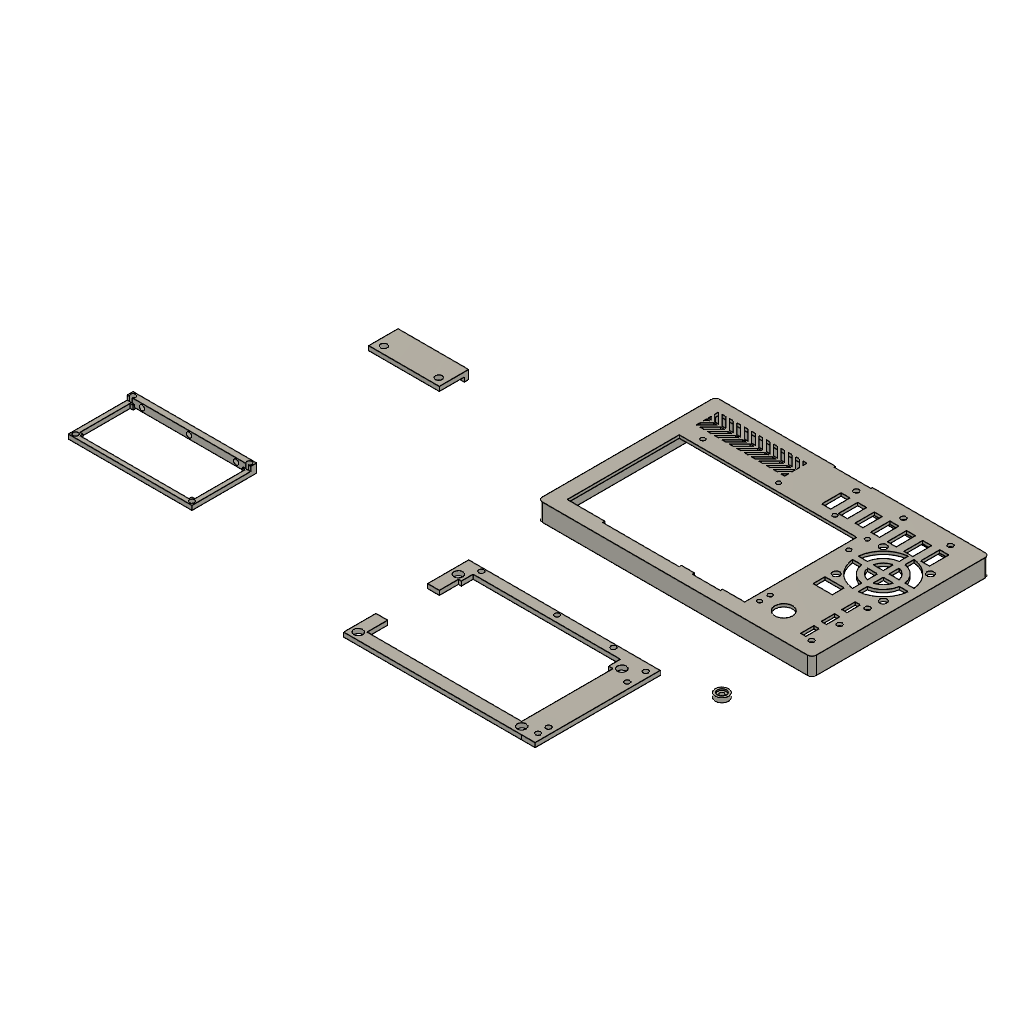
Cyberdeck V1.0 (Autodesk Fusion 360 design; units mm, degrees)
part number: 2026-10-02-13-29-24-381
part number: 2026-10-02-20-17-14-909
part number: 2026-10-03-23-10-58-900
part number: 2026-10-04-18-41-37-059
part number: 2026-10-05-15-20-19-140
part number: 2026-10-05-15-29-06-414
Autodesk Fusion 360 part; units mm, degrees
(part 1 of 2)
sketch "Sketch1" plane through (0, 0, 0) normal (0, 1, 0) x (1, 0, 0)
  line L0 (3, 0) -> (183.15, 0)
  line L1 (186.15, 3) -> (186.15, 117.65)
  line L2 (183.15, 120.65) -> (3, 120.65)
  line L3 (0, 117.65) -> (0, 3)
  arc A0 (3, 120.65) -> (0, 117.65) centre (3, 117.65) ccw
  arc A1 (0, 3) -> (3, 0) centre (3, 3) ccw
  arc A2 (186.15, 117.65) -> (183.15, 120.65) centre (183.15, 117.65) ccw
  arc A3 (183.15, 0) -> (186.15, 3) centre (183.15, 3) ccw
  line L4 (93.075, 120.65) -> (93.075, 0) construction
  line L5 (0, 60.325) -> (186.15, 60.325) construction
  line L6 (0, 80) -> (10, 80) construction
  line L7 (10, 80) -> (10, 60.325) construction
  line L8 (131.5, 0) -> (131.5, 10) construction
  line L9 (131.5, 10) -> (11, 10)
  line L10 (11, 10) -> (11, 86) construction
  line L11 (11, 86) -> (131.5, 86)
  line L12 (131.5, 86) -> (131.5, 10)
  line L13 (93.075, 114.9634) -> (105.575, 114.9634) construction
  line L14 (106.575, 120.65) -> (106.575, 123.65) construction
  line L15 (106.575, 120.65) -> (81.575, 120.65)
  line L16 (81.575, 120.65) -> (81.575, 119.65)
  line L17 (81.575, 119.65) -> (106.575, 119.65)
  line L18 (106.575, 119.65) -> (106.575, 120.65)
  line L19 (131.5, 15.7843) -> (116.5, 15.7843) construction
  line L20 (115.5, 10) -> (115.5, 8.5) construction
  line L21 (115.5, 8.5) -> (96.5, 8.5)
  line L22 (96.5, 8.5) -> (96.5, 10)
  line L23 (96.5, 10) -> (115.5, 10)
  line L24 (115.5, 10) -> (115.5, 8.5)
  line L25 (96.5, 8.5) -> (85.5, 8.5) construction
  line L26 (87.5, 10) -> (35.5, 10)
  line L27 (35.5, 10) -> (35.5, 8.5)
  line L28 (35.5, 8.5) -> (87.5, 8.5)
  line L29 (87.5, 8.5) -> (87.5, 10)
  line L30 (182.15, 116.65) -> (4, 116.65)
  line L31 (4, 116.65) -> (4, 4)
  line L32 (4, 4) -> (182.15, 4)
  line L33 (182.15, 4) -> (182.15, 116.65)
  line L34 (181.1, 53.5082) -> (141.1, 53.5082) construction
  line L35 (141.1, 53.5082) -> (141.1, 93.5082) construction
  line L36 (141.1, 93.5082) -> (181.1, 93.5082) construction
  line L37 (181.1, 93.5082) -> (181.1, 53.5082) construction
  line L38 (181.1, 73.5082) -> (141.1, 73.5082) construction
  line L39 (161.1, 93.5082) -> (161.1, 53.5082) construction
  line L40 (177.1, 53.5082) -> (177.1, 57.5082) construction
  circle A4 centre (177.1, 57.5082) radius 2.4
  line L41 (141.1, 57.4958) -> (145.1, 57.4958) construction
  line L42 (145.1, 53.5082) -> (145.1, 57.5082) construction
  circle A5 centre (145.1, 57.5082) radius 2.4
  circle A6 centre (145.1, 89.5082) radius 2.4
  circle A7 centre (177.1, 89.5082) radius 2.4
  line L43 (159.1, 92.4026) -> (159.1, 86.3534)
  line L44 (159.1, 82.2831) -> (159.1, 75.5082)
  line L45 (163.1, 92.4026) -> (163.1, 86.3534)
  line L46 (163.1, 82.2831) -> (163.1, 75.5082)
  line L47 (163.1, 71.5082) -> (163.1, 64.7332)
  line L48 (163.1, 60.6629) -> (163.1, 54.6137)
  line L49 (159.1, 71.5082) -> (159.1, 64.7332)
  line L50 (159.1, 60.6629) -> (159.1, 54.6137)
  line L51 (179.9944, 71.5082) -> (173.9452, 71.5082)
  arc A8 (163.1, 64.7332) -> (169.875, 71.5082) centre (161.1, 73.5082) ccw
  arc A9 (169.875, 75.5082) -> (163.1, 82.2831) centre (161.1, 73.5082) ccw
  arc A10 (163.1, 60.6629) -> (173.9452, 71.5082) centre (161.1, 73.5082) ccw
  arc A11 (173.9452, 75.5082) -> (163.1, 86.3534) centre (161.1, 73.5082) ccw
  line L52 (179.9944, 75.5082) -> (173.9452, 75.5082)
  line L53 (169.875, 75.5082) -> (163.1, 75.5082)
  line L54 (148.2548, 71.5082) -> (142.2056, 71.5082)
  arc A12 (159.1, 86.3534) -> (148.2548, 75.5082) centre (161.1, 73.5082) ccw
  arc A13 (148.2548, 71.5082) -> (159.1, 60.6629) centre (161.1, 73.5082) ccw
  arc A14 (159.1, 82.2831) -> (152.325, 75.5082) centre (161.1, 73.5082) ccw
  arc A15 (152.325, 71.5082) -> (159.1, 64.7332) centre (161.1, 73.5082) ccw
  line L55 (159.1, 75.5082) -> (152.325, 75.5082)
  line L56 (148.2548, 75.5082) -> (142.2056, 75.5082)
  arc A16 (163.1, 54.6137) -> (179.9944, 71.5082) centre (161.1, 73.5082) ccw
  arc A17 (142.2056, 71.5082) -> (159.1, 54.6137) centre (161.1, 73.5082) ccw
  arc A18 (179.9944, 75.5082) -> (163.1, 92.4026) centre (161.1, 73.5082) ccw
  arc A19 (159.1, 92.4026) -> (142.2056, 75.5082) centre (161.1, 73.5082) ccw
  line L57 (169.875, 71.5082) -> (163.1, 71.5082)
  line L58 (159.1, 71.5082) -> (152.325, 71.5082)
  line L59 (9.9994, 116.65) -> (9.9994, 112.65) construction
  line L60 (9.9994, 112.65) -> (5.9994, 112.65) construction
  line L61 (9.9994, 112.65) -> (69.9994, 112.65)
  line L62 (69.9994, 112.65) -> (69.9994, 97.65)
  line L63 (69.9994, 97.65) -> (9.9994, 97.65)
  line L64 (9.9994, 97.65) -> (9.9994, 112.65)
  line L65 (9.9994, 105.15) -> (69.9994, 105.15) construction
  line L66 (39.9994, 112.65) -> (39.9994, 97.65) construction
  line L67 (9.9994, 112.65) -> (17.4994, 105.15)
  line L68 (9.9994, 112.65) -> (20.6066, 112.65) construction
  line L69 (19.9994, 105.1486) -> (12.498, 112.65)
  line L70 (19.9994, 105.1486) -> (9.3934, 105.1486) construction
  line L71 (14.9994, 105.1486) -> (9.9994, 110.1486)
  line L72 (14.9994, 105.1486) -> (7.9289, 105.1486) construction
  line L73 (12.4994, 105.1486) -> (9.9994, 107.6486)
  line L74 (12.4994, 105.1486) -> (8.9645, 105.1486) construction
  line L75 (22.4994, 105.149) -> (14.9984, 112.65)
  line L76 (22.4994, 105.149) -> (11.8934, 105.149) construction
  line L77 (24.9994, 105.1493) -> (17.4987, 112.65)
  line L78 (24.9994, 105.1493) -> (14.3934, 105.1493) construction
  line L79 (27.4994, 105.1496) -> (19.9991, 112.65)
  line L80 (27.4994, 105.1496) -> (16.8934, 105.1496) construction
  line L81 (29.9994, 105.15) -> (22.4994, 112.65)
  line L82 (29.9994, 105.15) -> (19.3934, 105.15) construction
  line L83 (32.4994, 105.15) -> (24.9994, 112.65)
  line L84 (32.4994, 105.15) -> (21.8934, 105.15) construction
  line L85 (34.9994, 105.15) -> (27.4994, 112.65)
  line L86 (34.9994, 105.15) -> (24.3934, 105.15) construction
  line L87 (37.4994, 105.15) -> (29.9994, 112.65)
  line L88 (37.4994, 105.15) -> (26.8934, 105.15) construction
  line L89 (39.9994, 105.15) -> (32.5001, 112.65)
  line L90 (12.4994, 105.1514) -> (9.9994, 102.6514)
  line L91 (14.9994, 105.1514) -> (9.9994, 100.1514)
  line L92 (9.9994, 97.65) -> (17.4994, 105.15)
  line L93 (19.9994, 105.1514) -> (12.498, 97.65)
  line L94 (22.4994, 105.151) -> (14.9984, 97.65)
  line L95 (24.9994, 105.1507) -> (17.4987, 97.65)
  line L96 (27.4994, 105.1504) -> (19.9991, 97.65)
  line L97 (29.9994, 105.15) -> (22.4994, 97.65)
  line L98 (32.4994, 105.15) -> (24.9994, 97.65)
  line L99 (34.9994, 105.15) -> (27.4994, 97.65)
  line L100 (37.4994, 105.15) -> (29.9994, 97.65)
  line L101 (39.9994, 105.15) -> (32.5001, 97.65)
  line L102 (44.9994, 105.15) -> (37.5001, 112.65)
  line L103 (44.9994, 105.15) -> (37.5001, 97.65)
  line L104 (42.4994, 105.15) -> (34.9994, 97.65)
  line L105 (42.4994, 105.15) -> (34.9994, 112.65)
  line L106 (49.9994, 105.15) -> (42.5001, 112.65)
  line L107 (49.9994, 105.15) -> (42.5001, 97.65)
  line L108 (47.4994, 105.15) -> (39.9994, 97.65)
  line L109 (47.4994, 105.15) -> (39.9994, 112.65)
  line L110 (54.9994, 105.15) -> (47.5001, 112.65)
  line L111 (54.9994, 105.15) -> (47.5001, 97.65)
  line L112 (52.4994, 105.15) -> (44.9994, 97.65)
  line L113 (52.4994, 105.15) -> (44.9994, 112.65)
  line L114 (59.9994, 105.15) -> (52.5001, 112.65)
  line L115 (59.9994, 105.15) -> (52.5001, 97.65)
  line L116 (57.4994, 105.15) -> (49.9994, 97.65)
  line L117 (57.4994, 105.15) -> (49.9994, 112.65)
  line L118 (64.9994, 105.15) -> (57.5001, 112.65)
  line L119 (64.9994, 105.15) -> (57.5001, 97.65)
  line L120 (62.4994, 105.15) -> (54.9994, 97.65)
  line L121 (62.4994, 105.15) -> (54.9994, 112.65)
  line L122 (69.9994, 105.15) -> (62.5001, 112.65)
  line L123 (69.9994, 105.15) -> (62.5001, 97.65)
  line L124 (67.4994, 105.15) -> (59.9994, 97.65)
  line L125 (67.4994, 105.15) -> (59.9994, 112.65)
  line L126 (64.9998, 112.65) -> (69.9994, 107.6504)
  line L127 (64.9998, 112.65) -> (72.0711, 112.65) construction
  line L128 (67.5003, 112.65) -> (69.9994, 110.1508)
  line L129 (67.5003, 112.65) -> (71.0353, 112.65) construction
  line L130 (67.5003, 97.65) -> (69.9994, 100.1492)
  line L131 (64.9998, 97.65) -> (69.9994, 102.6496)
  line L132 (9.849, 105.1486) -> (9.849, 105.6486) construction
  line L133 (9.9994, 105.65) -> (69.9994, 105.65)
  line L134 (69.9994, 105.65) -> (69.9994, 104.65)
  line L135 (69.9994, 104.65) -> (9.9994, 104.65)
  line L136 (9.9994, 104.65) -> (9.9994, 105.65)
  circle A20 centre (149, 18) radius 6
  line L137 (149, 18) -> (149, 39) construction
  line L138 (149, 39) -> (149, -1.5) construction
  line L139 (149, 39) -> (157.5, 39) construction
  line L140 (157.5, 39) -> (140.5, 39) construction
  line L141 (140.5, 39) -> (140.5, -2) construction
  line L142 (140.5, -2) -> (157.5, -2) construction
  line L143 (157.5, -2) -> (157.5, 39) construction
  line L144 (10, 86) -> (130.5, 86)
  line L145 (130.5, 45.25) -> (130.5, 69.25)
  line L146 (135.5, 16) -> (130.5, 16) construction
  line L147 (130.5, 86) -> (130.5, 10)
  line L148 (130.5, 86) -> (130.5, 91) construction
  line L149 (135.5, 16) -> (135.5, 10) construction
  line L150 (135.5, 16) -> (135.5, 31) construction
  line L151 (177.1, 57.5082) -> (182.15, 57.5082) construction
  line L152 (179.5, 57.5082) -> (180.4, 57.5082) construction
  line L153 (145.1, 57.4958) -> (161.1, 73.5082) construction
  line L154 (177.1, 57.5082) -> (161.1, 73.5082) construction
  line L155 (145.1, 89.5082) -> (161.1, 73.5082) construction
  line L156 (161.1, 73.5082) -> (177.1, 89.5082) construction
  circle A21 centre (71.9476, 91.55) radius 1.5
  line L157 (9.5, 91.55) -> (139.6028, 91.55) construction
  circle A22 centre (110.2113, 91.55) radius 1.5
  circle A23 centre (20.5456, 91.55) radius 1.5
  circle A24 centre (135.2814, 88.5158) radius 1.5
  circle A25 centre (135.2497, 75.9806) radius 1.5
  circle A26 centre (135.1147, 22.6259) radius 1.5
  line L158 (139.6028, 8.2) -> (139.6028, 95.3) construction
  line L159 (135.2986, 95.3) -> (135.0794, 8.6911) construction
  circle A27 centre (135.0967, 15.5182) radius 1.5
  line L160 (183.15, 118.65) -> (3, 118.65)
  arc A28 (3, 118.65) -> (2, 117.65) centre (3, 117.65) ccw
  line L161 (2, 117.65) -> (2, 3)
  arc A29 (2, 3) -> (3, 2) centre (3, 3) ccw
  line L162 (3, 2) -> (183.15, 2)
  arc A30 (183.15, 2) -> (184.15, 3) centre (183.15, 3) ccw
  line L163 (184.15, 3) -> (184.15, 117.65)
  arc A31 (184.15, 117.65) -> (183.15, 118.65) centre (183.15, 117.65) ccw
  line L164 (93.15, 117.45) -> (93.15, 108.85)
  circle A32 centre (103.15, 113.15) radius 1.75
  circle A33 centre (135.15, 113.15) radius 1.75
  circle A34 centre (167.15, 113.15) radius 1.75
  line L165 (177.15, 117.45) -> (93.15, 117.45)
  line L166 (177.15, 113.15) -> (93.15, 113.15) construction
  line L167 (135.15, 108.85) -> (135.15, 117.45) construction
  line L168 (177.15, 108.85) -> (177.15, 117.45)
  line L169 (93.15, 108.85) -> (177.15, 108.85)
  line L170 (135.15, 108.85) -> (135.15, 106.85) construction
  line L171 (93.15, 106.85) -> (177.15, 106.85) construction
  line L172 (181.15, 93.85) -> (172.15, 93.85) construction
  line L173 (93.15, 93.85) -> (102.15, 93.85) construction
  line L174 (172.15, 93.85) -> (166.15, 93.85)
  line L175 (166.15, 93.85) -> (166.15, 106.85)
  line L176 (166.15, 106.85) -> (172.15, 106.85)
  line L177 (172.15, 106.85) -> (172.15, 93.85)
  line L178 (173, 53) -> (173, 5)
  circle A35 centre (176, 29) radius 1.75
  line L179 (179, 5) -> (179, 53)
  line L180 (179, 53) -> (173, 53)
  line L181 (179, 29) -> (173, 29) construction
  line L182 (176, 53) -> (176, 5)
  line L183 (173, 5) -> (176, 5)
  line L184 (176, 5) -> (176, 53)
  circle A36 centre (176, 48) radius 1.75
  circle A37 centre (176, 10) radius 1.75
  line L185 (173, 5) -> (179, 5)
  line L186 (173, 53) -> (173, 5)
  line L187 (176, 53) -> (173, 53)
  line L188 (173, 29) -> (171.5, 29) construction
  line L189 (143, 52) -> (156, 52)
  line L190 (156, 52) -> (156, 44)
  line L191 (156, 44) -> (143, 44)
  line L192 (143, 44) -> (143, 52)
  line L193 (172, 5) -> (172, 10.5) construction
  line L194 (172, 53) -> (172, 47.5) construction
  line L195 (171.5, 10.5) -> (171.5, 47.5) construction
  line L196 (171.5, 10.5) -> (168, 10.5)
  line L197 (168, 10.5) -> (168, 19.5)
  line L198 (168, 19.5) -> (171.5, 19.5)
  line L199 (171.5, 19.5) -> (171.5, 10.5)
  line L200 (168, 19.5) -> (168, 24.5) construction
  line L201 (168, 24.5) -> (171.5, 24.5)
  line L202 (171.5, 24.5) -> (171.5, 33.5)
  line L203 (171.5, 33.5) -> (168, 33.5)
  line L204 (168, 33.5) -> (168, 24.5)
  line L205 (168, 33.5) -> (168, 38.5) construction
  line L206 (168, 38.5) -> (171.5, 38.5)
  line L207 (171.5, 38.5) -> (171.5, 47.5)
  line L208 (171.5, 47.5) -> (168, 47.5)
  line L209 (168, 47.5) -> (168, 38.5)
  line L210 (10, 86) -> (10, 10)
  line L211 (11, 10) -> (10, 10)
  line L212 (166.15, 93.85) -> (160.85, 93.85) construction
  line L213 (160.85, 93.85) -> (154.85, 93.85)
  line L214 (154.85, 93.85) -> (154.85, 106.5235)
  line L215 (154.85, 106.5235) -> (160.85, 106.5235)
  line L216 (160.85, 106.5235) -> (160.85, 93.85)
  line L217 (154.85, 93.85) -> (149.55, 93.85) construction
  line L218 (149.55, 93.85) -> (143.55, 93.85)
  line L219 (143.55, 93.85) -> (143.55, 106.85)
  line L220 (143.55, 106.85) -> (149.55, 106.85)
  line L221 (149.55, 106.85) -> (149.55, 93.85)
  line L222 (143.55, 93.85) -> (138.25, 93.85) construction
  line L223 (138.25, 93.85) -> (132.25, 93.85)
  line L224 (132.25, 93.85) -> (132.25, 106.85)
  line L225 (132.25, 106.85) -> (138.25, 106.85)
  line L226 (138.25, 106.85) -> (138.25, 93.85)
  line L227 (132.25, 93.85) -> (126.95, 93.85) construction
  line L228 (126.95, 93.85) -> (121.65, 93.85)
  line L229 (121.65, 93.85) -> (121.65, 106.85)
  line L230 (121.65, 106.85) -> (126.95, 106.85)
  line L231 (126.95, 106.85) -> (126.95, 93.85)
  line L232 (121.65, 93.85) -> (116.35, 93.85) construction
  line L233 (116.35, 93.85) -> (110.35, 93.85)
  line L234 (110.35, 93.85) -> (110.35, 106.85)
  line L235 (110.35, 106.85) -> (116.35, 106.85)
  line L236 (116.35, 106.85) -> (116.35, 93.85)
  line L237 (110.35, 93.85) -> (105.05, 93.85) construction
  line L238 (105.05, 93.85) -> (99.05, 93.85)
  line L239 (99.05, 93.85) -> (99.05, 106.85)
  line L240 (99.05, 106.85) -> (105.05, 106.85)
  line L241 (105.05, 106.85) -> (105.05, 93.85)
  line L242 (106.575, 120.65) -> (81.575, 120.65)
  line L243 (3, 0) -> (183.15, 0)
  line L244 (81.575, 119.65) -> (106.575, 119.65)
  line L245 (183.15, 120.65) -> (3, 120.65)
  line L246 (106.575, 119.65) -> (106.575, 120.65)
  line L247 (93.075, 120.65) -> (93.075, 0) construction
  arc A38 (3, 120.65) -> (0, 117.65) centre (3, 117.65) ccw
  arc A39 (0, 3) -> (3, 0) centre (3, 3) ccw
  line L248 (106.575, 120.65) -> (106.575, 123.65) construction
  line L249 (178.15, 8) -> (178.15, 112.65)
  arc A40 (183.15, 0) -> (186.15, 3) centre (183.15, 3) ccw
  line L250 (186.15, 60.325) -> (178.15, 60.325) construction
  arc A41 (186.15, 117.65) -> (183.15, 120.65) centre (183.15, 117.65) ccw
  line L251 (0, 117.65) -> (0, 3)
  line L252 (93.075, 112.65) -> (93.075, 120.65) construction
  line L253 (186.15, 3) -> (186.15, 117.65)
  line L254 (8, 112.65) -> (8, 8)
  line L255 (178.15, 112.65) -> (8, 112.65)
  line L256 (81.575, 120.65) -> (81.575, 119.65)
  line L257 (8, 8) -> (178.15, 8)
  line L258 (0, 60.325) -> (186.15, 60.325) construction
  line L259 (5, 5) -> (181.15, 5)
  line L260 (181.15, 5) -> (181.15, 115.65)
  line L261 (181.15, 115.65) -> (5, 115.65)
  line L262 (5, 115.65) -> (5, 5)
  line L263 (106.575, 119.65) -> (106.575, 115.65)
  line L264 (81.575, 119.65) -> (81.575, 115.65)
  point P0 (186.15, 0)
  point P1 (0, 120.65)
  point P2 (139.6028, 30.2)
  point P3 (139.6028, 73.234)
  point P4 (93.075, 120.65)
  dimension "d1" = 186.15
  dimension "d2" = 120.65
  dimension "d3" = 3
  dimension "d6" = 10
  dimension "d7" = 76
  dimension "d10" = 12.5
  dimension "d12" = 25
  dimension "d13" = 1
  dimension "d14" = 15
  dimension "d15" = 1.5
  dimension "d16" = 19
  dimension "d17" = 11
  dimension "d18" = 52
  dimension "d19" = 1.5
  dimension "d21" = -4
  dimension "d24" = 40
  dimension "d25" = 40
  dimension "d27" = 38
  dimension "d29" = 4
  dimension "d30" = 4.8
  dimension "d31" = 4
  dimension "d32" = 4
  dimension "d33" = 4.8
  dimension "d37" = 4
  dimension "d38" = 4
  dimension "d39" = 4
  dimension "d42" = 4
  dimension "d43" = 4
  dimension "d44" = 60
  dimension "d45" = 15
  dimension "d46" = 45
  dimension "d47" = 2.5
  dimension "d48" = 45
  dimension "d49" = 2.5
  dimension "d50" = 45
  dimension "d51" = 2.5
  dimension "d52" = 45
  dimension "d53" = 2.5
  dimension "d54" = 45
  dimension "d55" = 2.5
  dimension "d56" = 45
  dimension "d57" = 2.5
  dimension "d58" = 45
  dimension "d59" = 2.5
  dimension "d60" = 45
  dimension "d61" = 2.5
  dimension "d62" = 45
  dimension "d63" = 2.5
  dimension "d64" = 45
  dimension "d65" = 2.5
  dimension "d66" = 45
  dimension "d68" = 2.5
  dimension "d72" = 30
  dimension "d73" = 0
  dimension "d74" = 45
  dimension "d75" = 45
  dimension "d77" = 6
  dimension "d78" = 6
  dimension "d79" = 4
  dimension "d80" = 6
  dimension "d81" = 4
  dimension "d82" = 4
  dimension "d83" = 6
  dimension "d84" = 0.5
  dimension "d85" = 60
  dimension "d86" = 1
  dimension "d87" = 12
  dimension "d88" = 21
  dimension "d89" = 40.5
  dimension "d90" = 8.5
  dimension "d91" = 17
  dimension "d92" = 41
  dimension "d93" = -2
  dimension "d94" = 0.5
  dimension "d95" = 0.5
  dimension "d96" = 1
  dimension "d100" = 120.5
  dimension "d127" = 9.6
  dimension "d128" = 1.05
  dimension "d158" = 24
  dimension "d171" = 15
  dimension "d172" = 6
  dimension "d173" = 0.9
  dimension "d174" = 22.6274
  dimension "d175" = 22.6361
  dimension "d176" = 22.6274
  dimension "d177" = 22.6274
  dimension "d214" = 87.1
  dimension "d216" = 3
  dimension "d217" = 3
  dimension "d218" = 3
  dimension "d219" = 3
  dimension "d220" = 3
  dimension "d222" = 3
  dimension "d223" = 3
  dimension "d269" = 3.5
  dimension "d270" = 3.5
  dimension "d271" = 2
  dimension "d272" = 84
  dimension "d274" = 9
  dimension "d275" = 6
  dimension "d296" = 6
  dimension "d297" = 3.5
  dimension "d298" = 3.5
  dimension "d299" = 1.5
  dimension "d300" = 13
  dimension "d301" = 8
  dimension "d303" = 5.5
  dimension "d306" = 3.5
  dimension "d307" = 9
  dimension "d308" = 5
  dimension "d309" = 9
  dimension "d310" = 5
  dimension "d311" = 9
  dimension "d314" = 5.3
  dimension "d315" = 6
  dimension "d316" = 5.3
  dimension "d317" = 6
  dimension "d318" = 13
  dimension "d319" = 5.3
  dimension "d320" = 6
  dimension "d321" = 5.3
  dimension "d322" = 5.3
  dimension "d323" = 5.3
  dimension "d324" = 6
  dimension "d325" = 5.3
  dimension "d326" = 6
  dimension "d339" = -8
  dimension "d340" = 3
  dimension "d346" = 25
  dimension "d347" = 1
  dimension "d348" = -5
  constraint horizontal L0
  constraint vertical L1
  constraint horizontal L2
  constraint vertical L3
  constraint coincident P1 L2
  constraint coincident P1 L3
  constraint tangent L2 A0
  constraint tangent L3 A0
  constraint coincident origin L0
  constraint coincident origin L3
  constraint tangent L0 A1
  constraint tangent L3 A1
  constraint equal A0 A1
  constraint tangent L2 A2
  constraint tangent L1 A2
  constraint equal A0 A2
  constraint coincident P0 L1
  constraint coincident P0 L0
  constraint tangent L1 A3
  constraint tangent L0 A3
  constraint equal A0 A3
  constraint midpoint L2 P4
  constraint midpoint L0 L4.end
  constraint midpoint L3 L5.start
  constraint midpoint L1 L5.end
  constraint coincident L3 L6.start
  constraint perpendicular L3 L6
  constraint coincident L5 L7.end
  constraint perpendicular L5 L7
  constraint coincident L0 L8.start
  constraint perpendicular L0 L8
  constraint horizontal L9
  constraint vertical L10
  constraint horizontal L11
  constraint vertical L12
  constraint coincident L4 L13.start
  constraint perpendicular L4 L13
  constraint coincident L2 L14.start
  constraint perpendicular L2 L14
  constraint horizontal L15
  constraint vertical L16
  constraint horizontal L17
  constraint vertical L18
  constraint coincident L12 L19.start
  constraint perpendicular L12 L19
  constraint coincident L9 L20.start
  constraint perpendicular L9 L20
  constraint horizontal L21
  constraint vertical L22
  constraint horizontal L23
  constraint vertical L24
  constraint perpendicular L22 L25
  constraint horizontal L26
  constraint vertical L27
  constraint horizontal L28
  constraint vertical L29
  constraint coincident L9 L26.start
  constraint horizontal L34
  constraint vertical L35
  constraint horizontal L36
  constraint vertical L37
  constraint midpoint L37 L38.start
  constraint midpoint L35 L38.end
  constraint midpoint L36 L39.start
  constraint midpoint L34 L39.end
  constraint midpoint L38 A8.centre
  constraint coincident L34 L40.start
  constraint perpendicular L34 L40
  constraint coincident L40.end A4.centre
  constraint coincident L35 L41.start
  constraint perpendicular L35 L41
  constraint coincident L34 L42.start
  constraint perpendicular L34 L42
  constraint coincident L42.end A5.centre
  constraint symmetric L38 A4 A7
  constraint symmetric L38 A5 A6
  constraint perpendicular L34 L48
  constraint symmetric L39 L48.end L50.end
  constraint symmetric L39 L45.start L43.start
  constraint perpendicular L35 L56
  constraint symmetric L38 L56.end L54.end
  constraint collinear L53 L55
  constraint collinear L44 L49
  constraint collinear L46 L47
  constraint collinear L43 L44
  constraint collinear L45 L46
  constraint concentric A14 A19
  constraint concentric A12 A19
  constraint concentric A8 A15
  constraint concentric A10 A13
  constraint collinear L47 L48
  constraint collinear L49 L50
  constraint collinear L51 L57
  constraint concentric A8 A9
  constraint concentric A10 A11
  constraint collinear L52 L53
  constraint collinear L54 L58
  constraint concentric A12 A13
  constraint concentric A14 A15
  constraint collinear L55 L56
  constraint concentric A16 A17
  constraint concentric A17 A19
  constraint concentric A18 A19
  constraint collinear L57 L58
  constraint coincident L30 L59.start
  constraint perpendicular L30 L59
  constraint perpendicular L31 L60
  constraint horizontal L61
  constraint vertical L62
  constraint horizontal L63
  constraint vertical L64
  constraint midpoint L64 L65.start
  constraint midpoint L62 L65.end
  constraint midpoint L61 L66.start
  constraint midpoint L63 L66.end
  constraint horizontal L68
  constraint coincident L65 L67.end
  constraint horizontal L70
  constraint coincident L68 L69.end
  constraint horizontal L72
  constraint coincident L64 L71.end
  constraint horizontal L74
  constraint coincident L64 L73.end
  constraint horizontal L76
  constraint coincident L61 L75.end
  constraint horizontal L78
  constraint coincident L61 L77.end
  constraint horizontal L80
  constraint coincident L61 L79.end
  constraint coincident L65 L81.start
  constraint horizontal L82
  constraint coincident L61 L81.end
  constraint horizontal L84
  constraint coincident L61 L83.end
  constraint horizontal L86
  constraint coincident L61 L85.end
  constraint coincident L65 L87.start
  constraint horizontal L88
  constraint coincident L61 L87.end
  constraint midpoint L65 L89.start
  constraint coincident L61 L89.end
  constraint symmetric L59.end L65 L63.end
  constraint symmetric L65 L67.end L92.end
  constraint symmetric L65 L69.start L93.start
  constraint symmetric L65 L69.end L93.end
  constraint symmetric L65 L71.start L91.start
  constraint symmetric L65 L71.end L91.end
  constraint symmetric L65 L73.start L90.start
  constraint symmetric L65 L73.end L90.end
  constraint symmetric L65 L75.start L94.start
  constraint symmetric L65 L75.end L94.end
  constraint symmetric L65 L77.start L95.start
  constraint symmetric L65 L77.end L95.end
  constraint symmetric L65 L79.start L96.start
  constraint symmetric L65 L79.end L96.end
  constraint symmetric L65 L81.start L82.start
  constraint symmetric L65 L81.end L97.end
  constraint symmetric L65 L83.start L84.start
  constraint symmetric L65 L83.end L98.end
  constraint symmetric L65 L85.start L86.start
  constraint symmetric L65 L85.end L99.end
  constraint symmetric L65 L87.start L88.start
  constraint symmetric L65 L87.end L100.end
  constraint symmetric L65 L89.start L101.start
  constraint symmetric L65 L89.end L101.end
  constraint horizontal L127
  constraint coincident L61 L126.start
  constraint coincident L62 L126.end
  constraint horizontal L129
  constraint coincident L127 L128.start
  constraint coincident L62 L128.end
  constraint symmetric L65 L126.start L131.start
  constraint symmetric L65 L126.end L131.end
  constraint symmetric L65 L128.start L130.start
  constraint symmetric L65 L128.end L130.end
  constraint coincident L70 L132.start
  constraint coincident L72 L132.start
  constraint perpendicular L70 L132
  constraint horizontal L133
  constraint vertical L134
  constraint horizontal L135
  constraint vertical L136
  constraint coincident L64 L133.start
  constraint coincident A20.centre L137.start
  constraint vertical L137
  constraint parallel L137 L138
  constraint perpendicular L138 L139
  constraint horizontal L140
  constraint vertical L141
  constraint horizontal L142
  constraint vertical L143
  constraint horizontal L144
  constraint vertical L147
  constraint vertical L145
  constraint coincident L145.end L147
  constraint perpendicular L144 L148
  constraint coincident L146.end L147
  constraint perpendicular L146 L147
  constraint perpendicular L146 L150
  constraint coincident L33 L151.end
  constraint perpendicular L33 L151
  constraint coincident L151 L152.start
  constraint coincident A4 L152.start
  constraint perpendicular L33 L152
  constraint coincident A8.centre A9.centre
  constraint coincident A6.centre L155.start
  constraint coincident A7.centre L156.end
  constraint coincident A25.centre L159
  constraint coincident A24.centre L159
  constraint coincident L157.end L158
  constraint perpendicular L157 L158
  constraint coincident A22.centre L157
  constraint coincident A21.centre L157
  constraint coincident A23.centre L157
  constraint coincident A27.centre L159
  constraint coincident A26.centre L159
  constraint coincident P3 L158
  constraint coincident P2 L158
  constraint horizontal L165
  constraint vertical L164
  constraint horizontal L169
  constraint vertical L168
  constraint midpoint L166.start L168
  constraint midpoint L166.end L164
  constraint midpoint L167.start L169
  constraint midpoint L167.end L165
  constraint coincident A34.centre L166
  constraint midpoint A33.centre L166
  constraint symmetric A32 A34 L167
  constraint perpendicular L169 L170
  constraint perpendicular L158 L172
  constraint horizontal L174
  constraint vertical L175
  constraint horizontal L176
  constraint vertical L177
  constraint coincident L178.start L180.end
  constraint coincident L182.start L184.end
  constraint coincident L182.end L183.end
  constraint midpoint L181.start L179
  constraint midpoint L181.end L186
  constraint midpoint A35.centre L181
  constraint coincident A36.centre L182
  constraint symmetric L181 A36 A37
  constraint perpendicular L186 L188
  constraint horizontal L189
  constraint vertical L190
  constraint horizontal L191
  constraint vertical L192
  constraint perpendicular L185 L193
  constraint symmetric L188 L193.start L194.start
  constraint symmetric L188 L193.end L194.end
  constraint perpendicular L181 L195
  constraint horizontal L196
  constraint vertical L197
  constraint horizontal L198
  constraint vertical L199
  constraint perpendicular L198 L200
  constraint horizontal L201
  constraint vertical L202
  constraint horizontal L203
  constraint vertical L204
  constraint perpendicular L203 L205
  constraint horizontal L206
  constraint vertical L207
  constraint horizontal L208
  constraint vertical L209
  constraint perpendicular L144 L210
  constraint perpendicular L175 L212
  constraint horizontal L213
  constraint vertical L214
  constraint horizontal L215
  constraint vertical L216
  constraint perpendicular L214 L217
  constraint horizontal L218
  constraint vertical L219
  constraint horizontal L220
  constraint vertical L221
  constraint perpendicular L219 L222
  constraint horizontal L223
  constraint vertical L224
  constraint horizontal L225
  constraint vertical L226
  constraint perpendicular L224 L227
  constraint horizontal L228
  constraint vertical L229
  constraint horizontal L230
  constraint vertical L231
  constraint perpendicular L229 L232
  constraint horizontal L233
  constraint vertical L234
  constraint horizontal L235
  constraint vertical L236
  constraint perpendicular L234 L237
  constraint horizontal L238
  constraint vertical L239
  constraint horizontal L240
  constraint vertical L241
  constraint horizontal L243
  constraint vertical L253
  constraint horizontal L245
  constraint vertical L251
  constraint tangent L245 A38
  constraint tangent A38 L251
  constraint tangent L243 A39
  constraint tangent A39 L251
  constraint equal A38 A39
  constraint tangent L245 A41
  constraint tangent A41 L253
  constraint equal A38 A41
  constraint tangent A40 L253
  constraint tangent L243 A40
  constraint equal A38 A40
  constraint midpoint L252.start L255
  constraint midpoint P4 L245
  constraint midpoint L4.end L243
  constraint midpoint L5.start L251
  constraint midpoint L5.end L253
  constraint perpendicular L253 L258
  constraint midpoint L250.end L249
  constraint horizontal L242
  constraint vertical L256
  constraint horizontal L244
  constraint vertical L246
  constraint coincident L261 L263.end
  constraint perpendicular L261 L263
  constraint perpendicular L30 L264
  measures "d1" distance of origin P0
  measures "d2" distance of origin P1
  measures "d3" radius of A0
  measures "d6" distance of L8.start L8.end
  measures "d7" distance of L8.end L11.end
  measures "d10" distance of L13.start L13.end
  measures "d12" distance of L14.start L15.end
  measures "d13" distance of L14.start L17.end
  measures "d14" distance of L19.start L19.end
  measures "d15" distance of L20.start L20.end
  measures "d16" distance of L20.end L21.end
  measures "d17" distance of L21.end L25.end
  measures "d18" distance of L26.start L26.end
  measures "d19" distance of L26.start L28.end
  measures "d24" distance of L34.start L34.end
  measures "d25" distance of L34.start L36.end
  measures "d27" diameter of A16
  measures "d29" distance of L40.start L40.end
  measures "d30" diameter of A4
  measures "d31" distance of L41.start L41.end
  measures "d32" distance of L42.start L42.end
  measures "d33" diameter of A5
  measures "d37" distance of L43 L45
  measures "d38" distance of L51 L52
  measures "d39" distance of A12 A14
  measures "d42" distance of L59.start L59.end
  measures "d43" distance of L59.end L60.end
  measures "d44" distance of L59.end L61.end
  measures "d45" distance of L59.end L63.end
  measures "d46" angle of L67 L68
  measures "d47" distance of L67.end L69.start
  measures "d48" angle of L69 L70
  measures "d49" distance of L67.end L71.start
  measures "d50" angle of L71 L72
  measures "d51" distance of L71.start L73.start
  measures "d52" angle of L73 L74
  measures "d53" distance of L69.start L75.start
  measures "d54" angle of L75 L76
  measures "d55" distance of L75.start L77.start
  measures "d56" angle of L77 L78
  measures "d57" distance of L77.start L79.start
  measures "d58" angle of L79 L80
  measures "d59" distance of L79.start L81.start
  measures "d60" angle of L81 L82
  measures "d61" distance of L81.start L83.start
  measures "d62" angle of L83 L84
  measures "d63" distance of L83.start L85.start
  measures "d64" angle of L85 L86
  measures "d65" distance of L85.start L87.start
  measures "d66" angle of L87 L88
  measures "d68" distance of L87.start L89.start
  measures "d74" angle of L126 L127
  measures "d75" angle of L128 L129
  measures "d77" distance of A12 A19
  measures "d78" distance of A11 A18
  measures "d79" distance of A9 A11
  measures "d80" distance of A10 A16
  measures "d81" distance of A8 A10
  measures "d82" distance of A13 A15
  measures "d83" distance of A13 A17
  measures "d84" distance of L132.start L132.end
  measures "d85" distance of L133.start L133.end
  measures "d86" distance of L133.start L135.end
  measures "d87" diameter of A20
  measures "d88" distance of A20.centre L137.end
  measures "d89" distance of L137.end L138.end
  measures "d90" distance of L137.end L139.end
  measures "d91" distance of L139.end L140.end
  measures "d92" distance of L139.end L142.end
  measures "d94" distance of L65 L135
  measures "d95" distance of L65 L133
  measures "d96" distance of L133 L135
  measures "d100" distance of L10.end L11.end
  measures "d127" distance of L12 L35
  measures "d128" distance of L33 L37
  measures "d158" distance of L145.end L145.start
  measures "d171" distance of L146.start L150.end
  measures "d172" distance of L146.start L149.end
  measures "d173" distance of L152.start L152.end
  measures "d174" distance of A6.centre A8.centre
  measures "d175" distance of L41.end A8.centre
  measures "d176" distance of L40.end A8.centre
  measures "d177" distance of A8.centre A7.centre
  measures "d214" distance of L158.start L158.end
  measures "d216" diameter of A25
  measures "d217" diameter of A24
  measures "d218" diameter of A22
  measures "d219" diameter of A21
  measures "d220" diameter of A23
  measures "d222" diameter of A27
  measures "d223" diameter of A26
  measures "d269" diameter of A34
  measures "d270" diameter of A33
  measures "d271" distance of L167.start L170.end
  measures "d272" distance of L171.start L171.end
  measures "d274" distance of L172.start L172.end
  measures "d275" distance of L172.end L174.end
  measures "d296" distance of L178.start L179.end
  measures "d297" diameter of A35
  measures "d298" diameter of A36
  measures "d299" distance of L181.end L188.end
  measures "d300" distance of L189.start L189.end
  measures "d301" distance of L189.start L191.end
  measures "d303" distance of L193.start L193.end
  measures "d306" distance of L195.start L196.end
  measures "d307" distance of L195.start L198.end
  measures "d308" distance of L197.end L200.end
  measures "d309" distance of L200.end L203.end
  measures "d310" distance of L203.end L205.end
  measures "d311" distance of L205.end L208.end
  measures "d314" distance of L174.end L212.end
  measures "d315" distance of L212.end L213.end
  measures "d316" distance of L213.end L217.end
  measures "d317" distance of L217.end L218.end
  measures "d318" distance of L217.end L220.end
  measures "d319" distance of L218.end L222.end
  measures "d320" distance of L222.end L223.end
  measures "d321" distance of L223.end L227.end
  measures "d322" distance of L227.end L228.end
  measures "d323" distance of L228.end L232.end
  measures "d324" distance of L232.end L233.end
  measures "d325" distance of L233.end L237.end
  measures "d326" distance of L237.end L238.end
  measures "d340" radius of A38
  measures "d346" distance of L14.start L15.end
  measures "d347" distance of L17.end L14.start
extrude "Extrude1" add sketch "Sketch1" along normal blind 2 contours L0 L1 L2 L3 A0 A1 A2 A3 L16 L18 L160 A28 L161 A29 L162 A30 L163 A31 L243 L245 L246 A38 A39 A40 A41 L251 L253 L256 L263 L264 | L17 L160 L244 L263 L264 | L30 L31 L32 L33 L160 A28 L161 A29 L162 A30 L163 A31 L165 L168 L263 L264 | L30 L160 L164 L165 L263 L264 | L30 L31 L32 L33 L168 L183 L185 L259 L260 L261 L262 L264 | L30 L164 L261 L264 | L30 L164 L165 L263 | L30 L165 L168 L263 | L30 L164 L261 L263 | L61 L164 L178 L186 L254 L255 L257 L259 L261 L262 | L30 L168 L261 L263 | L164 A32 A33 A34 L168 L255 L261 | L164 A32 A33 A34 L168 L169 L255 | A4 A7 L45 L48 L51 A10 A11 L52 A16 A18 L62 L63 L64 L134 L136 L164 L168 L169 L178 L180 L186 L187 L249 L254 L255 L257 | A4 A7 L51 L52 A16 A18 L168 L179 L180 L249 L255 L259 L260 L261 | L178 L182 L183 L184 L185 L186 L257 L259 | L61 L62 L126 L128 L255 | L178 A35 L180 L182 L184 A36 A37 L186 L187 L257 | L179 L180 L182 L184 L185 L249 L257 L259 | A35 L180 L182 L184 A36 A37 L249 L257 | L61 L122 L125 L133 L255 | L62 L122 L133 L134 | L122 L123 L124 L125 L133 L135 | L62 L123 L134 L135 | L61 L67 L69 L133 L255 | L61 L118 L121 L133 L255 | L118 L119 L124 L125 L133 L135 | L63 L123 L124 L135 | L64 L71 L73 L133 | L67 L69 L92 L93 L133 L135 | L67 L71 L91 L92 L133 L135 | L118 L119 L120 L121 L133 L135 | L62 L63 L130 L131 | L61 L75 L77 L133 L255 | L69 L75 L93 L94 L133 L135 | L71 L73 L90 L91 L133 L135 | L61 L114 L117 L133 L255 | L114 L115 L120 L121 L133 L135 | L63 L119 L120 L135 | L75 L77 L94 L95 L133 L135 | L64 L73 L90 L133 L135 L136 | L63 L92 L93 L135 | L114 L115 L116 L117 L133 L135 | L61 L79 L81 L133 L255 | L77 L79 L95 L96 L133 L135 | L64 L90 L91 L135 | L61 L110 L113 L133 L255 | L110 L111 L116 L117 L133 L135 | L63 L115 L116 L135 | L79 L81 L96 L97 L133 L135 | L63 L94 L95 L135 | L110 L111 L112 L113 L133 L135 | L61 L83 L85 L133 L255 | L81 L83 L97 L98 L133 L135 | L61 L106 L109 L133 L255 | L106 L107 L112 L113 L133 L135 | L63 L111 L112 L135 | L83 L85 L98 L99 L133 L135 | L63 L96 L97 L135 | L106 L107 L108 L109 L133 L135 | L61 L87 L89 L133 L255 | L85 L87 L99 L100 L133 L135 | L61 L102 L105 L133 L255 | L102 L103 L108 L109 L133 L135 | L63 L107 L108 L135 | L87 L89 L100 L101 L133 L135 | L63 L98 L99 L135 | L102 L103 L104 L105 L133 L135 | L89 L101 L104 L105 L133 L135 | L63 L103 L104 L135 | L63 L100 L101 L135 | L9 L11 L12 L145 L147 makes body 1
extrude "Extrude9" add sketch "Sketch1" against normal blind 10 contours L0 L1 L2 L3 A0 A1 A2 A3 L16 L18 L160 A28 L161 A29 L162 A30 L163 A31 L243 L245 L246 A38 A39 A40 A41 L251 L253 L256 L263 L264 | L30 L31 L32 L33 L160 A28 L161 A29 L162 A30 L163 A31 L165 L168 L263 L264 | L30 L31 L32 L33 L168 L183 L185 L259 L260 L261 L262 L264 | L30 L165 L168 L263 | L30 L168 L261 L263 bodies 1
copy_body "Body->Comp1" bodies 1 removing the originals makes body 2 in component "Base"
sketch "Sketch1 (2)" plane through (0, 0, 0) normal (0, 1, 0) x (1, 0, 0) in component "Screen Bracket "
  line L0 (140.1, -142) -> (140.1, -57)
  line L1 (10, -64) -> (131, -64)
  line L2 (10, -142) -> (10, -64)
  line L3 (131, -142) -> (10, -142)
  line L4 (131, -142) -> (131, -64)
  line L5 (131, -142) -> (140.1, -142)
  line L6 (135.7958, -54.9) -> (135.55, -142) construction
  circle A0 centre (135.739, -75.0164) radius 1.75
  circle A1 centre (135.7744, -62.4824) radius 1.75
  line L7 (10, -59.45) -> (140.1, -59.45) construction
  circle A2 centre (110.7113, -59.45) radius 1.75
  circle A3 centre (72.4476, -59.45) radius 1.75
  circle A4 centre (21.0456, -59.45) radius 1.75
  circle A5 centre (135.5684, -135.4787) radius 1.75
  circle A6 centre (135.5885, -128.3702) radius 1.75
  line L8 (140.1, -84.966) -> (131, -84.966)
  line L9 (131, -120) -> (140.1, -120)
  line L10 (10, -70) -> (15, -70) construction
  line L11 (131, -69) -> (126, -69) construction
  line L12 (123, -134) -> (123, -72)
  line L13 (18, -72) -> (123, -72)
  line L14 (18, -134) -> (18, -72)
  line L15 (123, -134) -> (18, -134)
  line L16 (131, -84.966) -> (123, -84.966)
  line L17 (131, -120) -> (123, -120)
  line L18 (126, -64) -> (126, -69) construction
  line L19 (15, -64) -> (15, -69) construction
  circle A7 centre (126, -69) radius 3
  circle A8 centre (15, -69) radius 3
  line L20 (70.5, -64) -> (70.5, -142) construction
  line L21 (10, -103) -> (131, -103) construction
  circle A9 centre (15, -137) radius 3
  circle A10 centre (126, -137) radius 3
  line L22 (20, -72) -> (20, -64)
  line L23 (120, -72) -> (120, -64)
  line L24 (123, -84.966) -> (18, -84.966) construction
  line L25 (123, -120) -> (18, -120) construction
  line L26 (18, -84.966) -> (10, -84.966)
  line L27 (18, -120) -> (10, -120)
  line L28 (10, -64) -> (10, -57)
  line L29 (10, -57) -> (140.1, -57)
  dimension "d185" = 78
  dimension "d186" = 121
  dimension "d195" = 9.1
  dimension "d196" = 3.5
  dimension "d197" = 3.5
  dimension "d198" = 3.5
  dimension "d199" = 3.5
  dimension "d200" = 3.5
  dimension "d202" = 3.5
  dimension "d203" = 3.5
  dimension "d205" = 5
  dimension "d206" = 5
  dimension "d207" = 8
  dimension "d208" = 5
  dimension "d209" = 5
  dimension "d210" = 6
  dimension "d211" = 6
  dimension "d224" = 34
  dimension "d286" = 7
  constraint horizontal L3
  constraint vertical L2
  constraint horizontal L1
  constraint perpendicular L1 L4
  constraint midpoint L5 L6.end
  constraint coincident L6 A0.centre
  constraint coincident L6 A1.centre
  constraint coincident L0 L7.end
  constraint perpendicular L0 L7
  constraint coincident L7 A2.centre
  constraint coincident L7 A3.centre
  constraint coincident L7 A4.centre
  constraint coincident L6 A5.centre
  constraint coincident L6 A6.centre
  constraint coincident L0 L8.start
  constraint coincident L4 L8.end
  constraint perpendicular L4 L8
  constraint coincident L4 L9.start
  constraint coincident L0 L9.end
  constraint perpendicular L0 L9
  constraint coincident L2 L10.start
  constraint perpendicular L2 L10
  constraint coincident L4 L11.start
  constraint perpendicular L4 L11
  constraint coincident L12 L16.end
  constraint perpendicular L12 L16
  constraint coincident L12 L17.end
  constraint perpendicular L12 L17
  constraint coincident L1 L18.start
  constraint perpendicular L1 L18
  constraint coincident L1 L19.start
  constraint perpendicular L1 L19
  constraint coincident L11.end L18.end
  constraint coincident L19.end A8.centre
  constraint midpoint L1 L20.start
  constraint midpoint L3 L20.end
  constraint midpoint L2 L21.start
  constraint midpoint L4 L21.end
  constraint symmetric A7 L21 A10
  constraint symmetric A8 L21 A9
  constraint coincident L13 L22.start
  constraint coincident L1 L22.end
  constraint perpendicular L1 L22
  constraint coincident L13 L23.start
  constraint coincident L1 L23.end
  constraint perpendicular L1 L23
  constraint coincident L14 L24.end
  constraint perpendicular L14 L24
  constraint coincident L14 L25.end
  constraint perpendicular L14 L25
  constraint coincident L2 L26.end
  constraint perpendicular L2 L26
  constraint coincident L2 L27.end
  constraint perpendicular L2 L27
  constraint perpendicular L1 L28
  constraint perpendicular L0 L29
  measures "d185" distance of L3.start L1.end
  measures "d186" distance of L1.start L1.end
  measures "d195" distance of L3.start L0.start
  measures "d196" diameter of A0
  measures "d197" diameter of A1
  measures "d198" diameter of A2
  measures "d199" diameter of A3
  measures "d200" diameter of A4
  measures "d202" diameter of A5
  measures "d203" diameter of A6
  measures "d205" distance of L10.start L10.end
  measures "d206" distance of L11.start L11.end
  measures "d208" distance of L18.start L11.end
  measures "d209" distance of L19.start L19.end
  measures "d210" diameter of A7
  measures "d211" diameter of A8
  measures "d224" distance of L19.end L21
  measures "d286" distance of L1.start L28.end
extrude "Extrude1'" add sketch "Sketch1 (2)" against normal blind 3 separate body contours L0 L4 L5 L9 | L0 L4 L8 L9 | L2 L3 L4 L12 L14 L15 L17 L27 | L0 L1 L4 L8 L28 L29 | L4 L12 L16 L17 | L1 L4 L12 L13 L16 L23 | L1 L2 L13 L14 L22 L26 makes body 3 in component "Screen Bracket "
sketch "Sketch1 (3)" plane through (0, 0, 0) normal (0, 1, 0) x (1, 0, 0) in component "screen numb retention thingys"
  circle A0 centre (175, -50) radius 3
  circle A1 centre (175, -50) radius 1.5
  circle A2 centre (175, -50) radius 4.5
  dimension "d225" = 6
  dimension "d226" = 3
  dimension "d229" = 9
  constraint concentric A0 A1
  constraint concentric A1 A2
  measures "d225" diameter of A0
  measures "d226" diameter of A1
  measures "d229" diameter of A2
extrude "Extrude1''" add sketch "Sketch1 (3)" along normal blind 1 separate body contours A2 makes body 4 in component "screen numb retention thingys"
extrude "Extrude2" add sketch "Sketch1 (3)" against normal blind 2 contours A0 | A2 bodies 4 in component "screen numb retention thingys"
sketch "Sketch1 (4)" plane through (0, 0, 0) normal (0, 1, 0) x (1, 0, 0) in component "USB A hub"
  line L0 (-200, -75) -> (-116, -75)
  line L1 (-116, -75) -> (-116, -119)
  line L2 (-116, -119) -> (-200, -119)
  line L3 (-200, -119) -> (-200, -75)
  line L4 (-195, -119) -> (-195, -116.5) construction
  line L5 (-200, -116.5) -> (-197.5, -116.5) construction
  circle A0 centre (-197.5, -116.5) radius 1.75
  line L6 (-158, -75) -> (-158, -119) construction
  line L7 (-200, -97) -> (-116, -97) construction
  circle A1 centre (-118.5, -116.5) radius 1.75
  circle A2 centre (-197.5, -77.5) radius 1.75
  circle A3 centre (-118.5, -77.5) radius 1.75
  line L8 (-120.1771, -116) -> (-195.8229, -116)
  line L9 (-197, -114.823) -> (-197, -79.177)
  line L10 (-195.8229, -78) -> (-120.1771, -78)
  line L11 (-119, -79.177) -> (-119, -114.823)
  line L12 (-197, -80) -> (-195, -80)
  line L13 (-195, -80) -> (-195, -78)
  line L14 (-121, -78) -> (-121, -80)
  line L15 (-121, -80) -> (-119, -80)
  line L16 (-119, -114) -> (-121, -114)
  line L17 (-121, -114) -> (-121, -116)
  line L18 (-197, -114) -> (-195, -114)
  line L19 (-195, -114) -> (-195, -116)
  dimension "d232" = 84
  dimension "d233" = 44
  dimension "d244" = 2.5
  dimension "d246" = 2.5
  dimension "d247" = 3.5
  dimension "d249" = 3
  dimension "d250" = 3
  dimension "d251" = 3
  dimension "d252" = 3
  constraint horizontal L0
  constraint vertical L1
  constraint horizontal L2
  constraint vertical L3
  constraint coincident L2 L4.start
  constraint perpendicular L2 L4
  constraint coincident L3 L5.start
  constraint perpendicular L3 L5
  constraint coincident L5.end A0.centre
  constraint midpoint L0 L6.start
  constraint midpoint L2 L6.end
  constraint midpoint L3 L7.start
  constraint midpoint L1 L7.end
  constraint symmetric A0 L6 A1
  constraint symmetric A0 L7 A2
  constraint symmetric L7 A1 A3
  constraint coincident A2 L10.start
  constraint coincident A2 L9.end
  constraint coincident A3 L11.start
  constraint coincident A3 L10.end
  constraint coincident A1 L11.end
  constraint coincident A1 L8.start
  constraint coincident A0 L8.end
  constraint coincident A0 L9.start
  constraint coincident L9 L12.start
  constraint perpendicular L9 L12
  constraint coincident L10 L13.end
  constraint perpendicular L10 L13
  constraint coincident L10 L14.start
  constraint perpendicular L10 L14
  constraint coincident L11 L15.end
  constraint perpendicular L11 L15
  constraint coincident L11 L16.start
  constraint perpendicular L11 L16
  constraint coincident L8 L17.end
  constraint perpendicular L8 L17
  constraint coincident L9 L18.start
  constraint perpendicular L9 L18
  constraint coincident L8 L19.end
  constraint perpendicular L8 L19
  measures "d232" distance of L0.start L0.end
  measures "d233" distance of L0.start L2.end
  measures "d244" distance of L4.start L4.end
  measures "d246" distance of L5.start L5.end
  measures "d247" diameter of A0
  measures "d249" distance of L2 L8
  measures "d250" distance of L3 L9
  measures "d251" distance of L0 L10
  measures "d252" distance of L1 L11
ref_plane "WorkPlane1" through (-158, 1.5, 75) normal (0, 0, -1) x (-1, 0, 0)
sketch "Sketch2" plane through (0, 0, 75) normal (0, 0, -1) x (-1, 0, 0) in component "USB A hub"
  line L0 (200, 3) -> (116, 3)
  line L1 (116, 3) -> (116, -2)
  line L2 (116, -2) -> (200, -2)
  line L3 (200, -2) -> (200, 3)
  line L4 (200, 0.5) -> (116, 0.5) construction
  line L5 (158, -2) -> (158, 3) construction
  circle A0 centre (190, 0.5) radius 1.75
  circle A1 centre (158, 0.5) radius 1.75
  circle A2 centre (126, 0.5) radius 1.75
  dimension "d257" = 3.5
  dimension "d258" = 3.5
  constraint horizontal L0
  constraint vertical L1
  constraint horizontal L2
  constraint vertical L3
  constraint midpoint L3 L4.start
  constraint midpoint L1 L4.end
  constraint midpoint L2 L5.start
  constraint midpoint L0 L5.end
  constraint coincident L4 A0.centre
  constraint midpoint L4 A1.centre
  constraint symmetric L5 A0 A2
  measures "d257" diameter of A0
  measures "d258" diameter of A1
extrude "Extrude1'''" add sketch "Sketch2" against normal blind 4 separate body makes body 5 in component "USB A hub"
extrude "Extrude2'" add sketch "Sketch1 (4)" against normal blind 3 contours L0 L1 L2 L3 | A0 L8 L9 L18 L19 | A1 L8 L11 L16 L17 | A2 L9 L10 L12 L13 | A3 L10 L11 L14 L15 bodies 5 in component "USB A hub"
extrude "Extrude3" cut sketch "Sketch1 (4)" along normal blind 3 contours A2 | A3 bodies 5 in component "USB A hub"
extrude "Extrude4" cut sketch "Sketch1 (4)" against normal blind 3 contours A2 | A3 bodies 5 in component "USB A hub"
extrude "Extrude5" cut sketch "Sketch2" against normal blind 4 contours A0 | A1 | A2 bodies 5 in component "USB A hub"